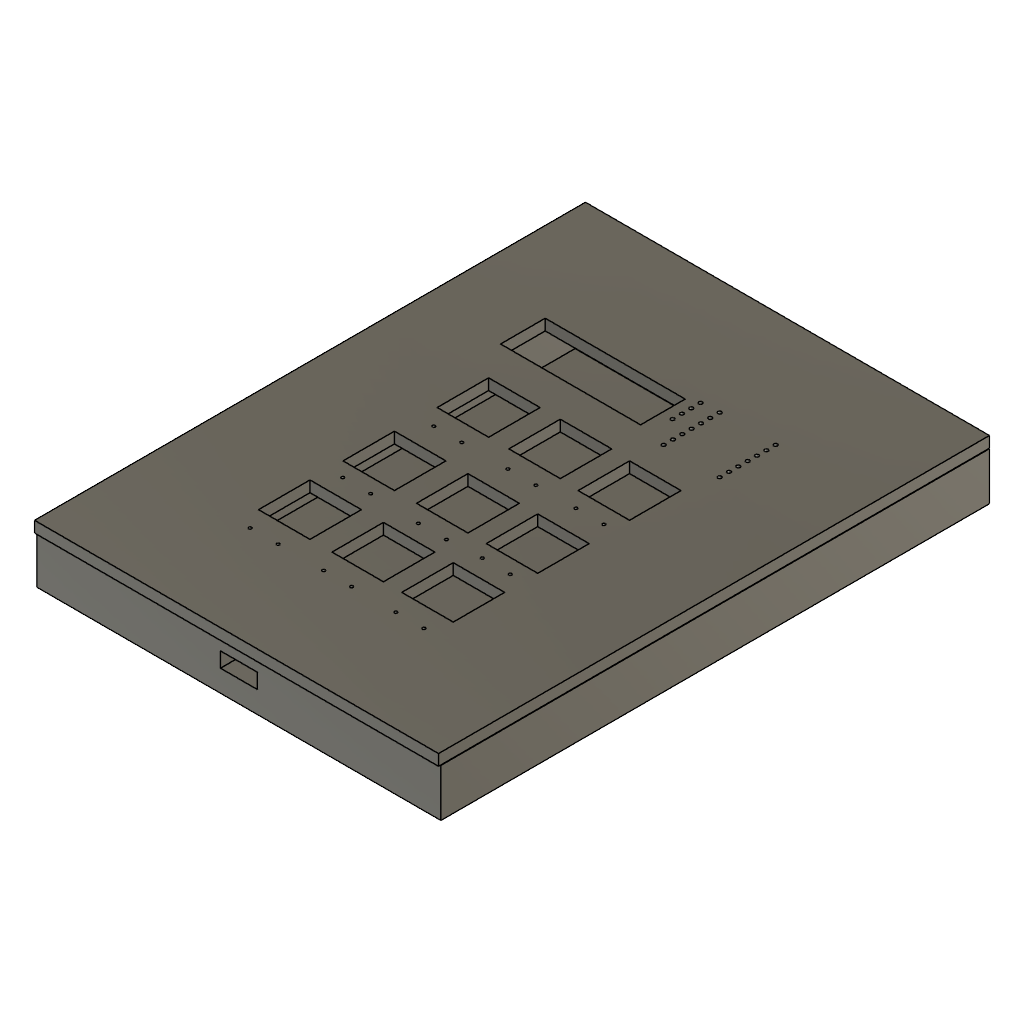
Macropad (Autodesk Fusion 360 design; units mm, degrees)
description: KiCad electronic assembly
part number: Macropad 1
part number: D_DO-35_SOD27_P7.62mm_Horizontal
Autodesk Fusion 360 part; units mm, degrees
sketch "Sketch1" plane through (0, 0, 0) normal (0, 0, 1) x (1, 0, 0)
  line L0 (86, -18, 1.51) -> (154.9049, -18, 1.51)
  line L1 (154.9049, -18, 1.51) -> (154.9049, -127.13, 1.51)
  line L2 (154.9049, -127.13, 1.51) -> (86, -127.13, 1.51)
  line L3 (86, -127.13, 1.51) -> (86, -18, 1.51)
  line L4 (69.7264, -4.9403) -> (170.0821, -4.9403)
  line L5 (170.0821, -4.9403) -> (170.0821, -139.9403)
  line L6 (170.0821, -139.9403) -> (69.7264, -139.9403)
  line L7 (69.7264, -139.9403) -> (69.7264, -4.9403)
  line L8 (-50, -10) -> (18.3484, -10)
  line L9 (18.3484, -10) -> (18.3484, -119.13)
  line L10 (18.3484, -119.13) -> (-50, -119.13)
  line L11 (-50, -119.13) -> (-50, -10)
  line L12 (-70, 10) -> (40, 10)
  line L13 (40, 10) -> (40, -139.3672)
  line L14 (40, -139.3672) -> (-70, -139.3672)
  line L15 (-70, -139.3672) -> (-70, 10)
  circle A0 centre (-60, 0) radius 1.45
  circle A1 centre (30, 0) radius 1.45
  circle A2 centre (30, -130) radius 1.45
  circle A3 centre (-60, -130) radius 1.45
  dimension "d1" = 109.13
  dimension "d2" = 135
  dimension "d3" = 109.13
  dimension "d5" = 2.9
  dimension "d6" = 2.9
  dimension "d7" = 2.9
  dimension "d8" = 2.9
  constraint horizontal L4
  constraint vertical L5
  constraint horizontal L6
  constraint vertical L7
  constraint horizontal L8
  constraint vertical L9
  constraint horizontal L10
  constraint vertical L11
  constraint horizontal L12
  constraint vertical L13
  constraint horizontal L14
  constraint vertical L15
  measures "d2" distance of L4.start L6.end
  measures "d3" distance of L8.start L10.end
  measures "d5" diameter of A0
  measures "d6" diameter of A1
  measures "d7" diameter of A2
  measures "d8" diameter of A3
extrude "Extrude1" add sketch "Sketch1" along normal blind 3 contours L8 L9 L10 L11 | L12 L13 L14 L15 makes body 1
sketch "Sketch2" plane through (0, 0, 3) normal (0, 0, 1) x (-1, 0, 0)
  circle A0 centre (60, 0) radius 1.45
  circle A1 centre (-30, 130) radius 1.45
  circle A2 centre (-30, 0) radius 1.45
  circle A3 centre (60, 130) radius 1.45
  line L0 (70, 139.3672) -> (-40, 139.3672)
  line L1 (-40, 139.3672) -> (-40, -10)
  line L2 (-40, -10) -> (70, -10)
  line L3 (70, -10) -> (70, 139.3672)
  line L4 (70, -10) -> (-40, -10)
  line L5 (-40, -10) -> (-40, 140)
  line L6 (-40, 140) -> (70, 140)
  line L7 (70, 140) -> (70, -10)
  line L8 (50, 12.8137) -> (-20.5069, 12.8137)
  line L9 (-20.5069, 12.8137) -> (-20.5069, 121.9437)
  line L10 (-20.5069, 121.9437) -> (50, 121.9437)
  line L11 (50, 121.9437) -> (50, 12.8137)
  dimension "d11" = 150
  dimension "d12" = 109.13
  constraint horizontal L4
  constraint vertical L5
  constraint horizontal L6
  constraint vertical L7
  constraint coincident L2.end L3.start
  constraint horizontal L8
  constraint vertical L9
  constraint horizontal L10
  constraint vertical L11
  measures "d11" distance of L2.end L6.end
  measures "d12" distance of L8.start L10.end
extrude "Extrude2" add sketch "Sketch2" along normal blind 10 contours L0 L1 L2 L3 L4 L5 L7 bodies 1
sketch "Sketch3" plane through (0, 0, 37.1086) normal (0, 0, 1) x (-1, 0, 0)
  line L0 (49.5053, 121.9681) -> (-19.4947, 121.9681)
  line L1 (-19.4947, 121.9681) -> (-19.4947, 12.9681)
  line L2 (-19.4947, 12.9681) -> (49.5053, 12.9681)
  line L3 (49.5053, 12.9681) -> (49.5053, 121.9681)
  circle A0 centre (38.8153, 112.4681) radius 0.4
  circle A1 centre (31.1953, 112.4681) radius 0.4
  circle A2 centre (40.1653, 99.9681) radius 0.85
  circle A3 centre (38.8953, 97.4281) radius 0.75
  circle A4 centre (35.0853, 99.9681) radius 2
  circle A5 centre (30.0053, 99.9681) radius 0.85
  circle A6 centre (32.5453, 94.8881) radius 0.75
  circle A7 centre (18.8153, 112.4681) radius 0.4
  circle A8 centre (21.0853, 99.9681) radius 0.85
  circle A9 centre (19.8153, 97.4281) radius 0.75
  circle A10 centre (16.0053, 99.9681) radius 2
  circle A11 centre (38.1253, 87.9681) radius 0.4
  circle A12 centre (30.5053, 87.9681) radius 0.4
  circle A13 centre (40.1653, 76.4681) radius 0.85
  circle A14 centre (38.8953, 73.9281) radius 0.75
  circle A15 centre (35.0853, 76.4681) radius 2
  circle A16 centre (30.0053, 76.4681) radius 0.85
  circle A17 centre (32.5453, 71.3881) radius 0.75
  circle A18 centre (17.0053, 88.4681) radius 0.4
  circle A19 centre (20.6653, 76.4681) radius 0.85
  circle A20 centre (19.3953, 73.9281) radius 0.75
  circle A21 centre (15.5853, 76.4681) radius 2
  circle A22 centre (11.1953, 112.4681) radius 0.4
  circle A23 centre (10.9253, 99.9681) radius 0.85
  circle A24 centre (13.4653, 94.8881) radius 0.75
  circle A25 centre (1.5853, 99.9681) radius 0.85
  circle A26 centre (0.3153, 97.4281) radius 0.75
  circle A27 centre (-0.8747, 112.4681) radius 0.4
  circle A28 centre (-8.4947, 112.4681) radius 0.4
  circle A29 centre (-3.4947, 99.9681) radius 2
  circle A30 centre (-6.0347, 94.8881) radius 0.75
  circle A31 centre (-8.5747, 99.9681) radius 0.85
  circle A32 centre (9.3853, 88.4681) radius 0.4
  circle A33 centre (0.1253, 87.9681) radius 0.4
  circle A34 centre (10.5053, 76.4681) radius 0.85
  circle A35 centre (13.0453, 71.3881) radius 0.75
  circle A36 centre (1.6653, 76.4681) radius 0.85
  circle A37 centre (0.3953, 73.9281) radius 0.75
  circle A38 centre (-7.4947, 87.9681) radius 0.4
  circle A39 centre (-3.4147, 76.4681) radius 2
  circle A40 centre (-5.9547, 71.3881) radius 0.75
  circle A41 centre (-8.4947, 76.4681) radius 0.85
  circle A42 centre (37.8153, 63.4681) radius 0.4
  circle A43 centre (30.1953, 63.4681) radius 0.4
  circle A44 centre (40.0853, 51.4681) radius 0.85
  circle A45 centre (35.0053, 51.4681) radius 2
  circle A46 centre (38.8153, 48.9281) radius 0.75
  circle A47 centre (29.9253, 51.4681) radius 0.85
  circle A48 centre (32.4653, 46.3881) radius 0.75
  circle A49 centre (17.6253, 63.4681) radius 0.4
  circle A50 centre (20.5853, 51.4681) radius 0.85
  circle A51 centre (15.5053, 51.4681) radius 2
  circle A52 centre (19.3153, 48.9281) radius 0.75
  circle A53 centre (10.0053, 63.4681) radius 0.4
  circle A54 centre (10.4253, 51.4681) radius 0.85
  circle A55 centre (12.9653, 46.3881) radius 0.75
  circle A56 centre (1.1653, 51.4681) radius 0.85
  circle A57 centre (-0.8747, 63.4681) radius 0.4
  circle A58 centre (-8.4947, 63.4681) radius 0.4
  circle A59 centre (-3.9147, 51.4681) radius 2
  circle A60 centre (-0.1047, 48.9281) radius 0.75
  circle A61 centre (-6.4547, 46.3881) radius 0.75
  circle A62 centre (-8.9947, 51.4681) radius 0.85
  circle A63 centre (2.1303, 36.5881) radius 0.5
  circle A64 centre (2.1303, 34.0481) radius 0.5
  circle A65 centre (7.0053, 29.2781) radius 0.5
  circle A66 centre (7.0053, 26.7381) radius 0.5
  circle A67 centre (7.0053, 24.1981) radius 0.5
  circle A68 centre (7.0053, 21.6581) radius 0.5
  circle A69 centre (2.1303, 31.5081) radius 0.5
  circle A70 centre (2.1303, 28.9681) radius 0.5
  circle A71 centre (2.1303, 26.4281) radius 0.5
  circle A72 centre (2.1303, 23.8881) radius 0.5
  circle A73 centre (2.1303, 21.3481) radius 0.5
  circle A74 centre (-13.1197, 36.5881) radius 0.5
  circle A75 centre (-13.1197, 34.0481) radius 0.5
  circle A76 centre (-13.1197, 31.5081) radius 0.5
  circle A77 centre (-13.1197, 28.9681) radius 0.5
  circle A78 centre (-13.1197, 26.4281) radius 0.5
  circle A79 centre (-13.1197, 23.8881) radius 0.5
  circle A80 centre (-13.1197, 21.3481) radius 0.5
  line L4 (70, -10) -> (-40, -10)
  line L5 (-40, -10) -> (-40, 140)
  line L6 (-40, 140) -> (70, 140)
  line L7 (70, 140) -> (70, -10)
  line L8 (-19.4947, 121.9681) -> (49.5053, 121.9681)
  line L9 (41.7673, 44.6043) -> (27.757, 44.6043)
  line L10 (27.757, 44.6043) -> (27.757, 58.6043)
  line L11 (27.757, 58.6043) -> (41.7673, 58.6043)
  line L12 (41.7673, 58.6043) -> (41.7673, 44.6043)
  line L13 (22.2576, 44.6043) -> (8.2473, 44.6043)
  line L14 (8.2473, 44.6043) -> (8.2473, 58.6043)
  line L15 (8.2473, 58.6043) -> (22.2576, 58.6043)
  line L16 (22.2576, 58.6043) -> (22.2576, 44.6043)
  line L17 (3, 45) -> (-11, 45)
  line L18 (-11, 45) -> (-11, 59)
  line L19 (-11, 59) -> (3, 59)
  line L20 (3, 59) -> (3, 45)
  line L21 (42, 70) -> (28, 70)
  line L22 (28, 70) -> (28, 84)
  line L23 (28, 84) -> (42, 84)
  line L24 (42, 84) -> (42, 70)
  line L25 (22, 70) -> (8, 70)
  line L26 (8, 70) -> (8, 84)
  line L27 (8, 84) -> (22, 84)
  line L28 (22, 84) -> (22, 70)
  line L29 (3, 70) -> (-11, 70)
  line L30 (-11, 70) -> (-11, 84)
  line L31 (-11, 84) -> (3, 84)
  line L32 (3, 84) -> (3, 70)
  line L33 (42, 93) -> (28, 93)
  line L34 (28, 93) -> (28, 107)
  line L35 (28, 107) -> (42, 107)
  line L36 (42, 107) -> (42, 93)
  line L37 (22, 93) -> (8, 93)
  line L38 (8, 93) -> (8, 107)
  line L39 (8, 107) -> (22, 107)
  line L40 (22, 107) -> (22, 93)
  line L41 (3, 93) -> (-11, 93)
  line L42 (-11, 93) -> (-11, 107)
  line L43 (-11, 107) -> (3, 107)
  line L44 (3, 107) -> (3, 93)
  line L45 (10, 35) -> (48.1118, 35)
  line L46 (48.1118, 35) -> (48.1118, 22.8531)
  line L47 (48.1118, 22.8531) -> (10, 22.8531)
  line L48 (10, 22.8531) -> (10, 35)
  dimension "d15" = 14
  constraint horizontal L4
  constraint vertical L5
  constraint horizontal L6
  constraint vertical L7
  constraint horizontal L8
  constraint coincident L0.end L1.start
  constraint horizontal L9
  constraint vertical L10
  constraint horizontal L11
  constraint vertical L12
  constraint horizontal L13
  constraint vertical L14
  constraint horizontal L15
  constraint vertical L16
  constraint horizontal L17
  constraint vertical L18
  constraint horizontal L19
  constraint vertical L20
  constraint horizontal L21
  constraint vertical L22
  constraint horizontal L23
  constraint vertical L24
  constraint horizontal L25
  constraint vertical L26
  constraint horizontal L27
  constraint vertical L28
  constraint horizontal L29
  constraint vertical L30
  constraint horizontal L31
  constraint vertical L32
  constraint horizontal L33
  constraint vertical L34
  constraint horizontal L35
  constraint vertical L36
  constraint horizontal L37
  constraint vertical L38
  constraint horizontal L39
  constraint vertical L40
  constraint horizontal L41
  constraint vertical L42
  constraint horizontal L43
  constraint vertical L44
  constraint horizontal L45
  constraint vertical L46
  constraint horizontal L47
  constraint vertical L48
  measures "d15" distance of L9.start L11.end
extrude "Extrude3" add sketch "Sketch3" along normal blind 3 separate body contours L0 L1 L2 L3 L8 | L4 L5 L6 L7 makes body 2
move_body "Move1" bodies 2 to x (1, 0, 0) y (0, 1, 0) z (0, 0, 1) at (0, 0, -3)
move_body "Move2" bodies 2 to x (1, 0, 0) y (0, 1, 0) z (0, 0, 1) at (0, 0, -20)
move_body "Move3" bodies 2 to x (1, 0, 0) y (0, 1, 0) z (0, 0, 1) at (0, 0, -1)
sketch "Sketch4" plane through (0, -139.3672, 0) normal (0, -1, 0) x (1, 0, 0)
  line L0 (-70, 0) -> (40, 0)
  line L1 (40, 0) -> (40, 13)
  line L2 (40, 13) -> (-70, 13)
  line L3 (-70, 13) -> (-70, 0)
  line L4 (-20, 10) -> (-9.9539, 10)
  line L5 (-9.9539, 10) -> (-9.9539, 5.9174)
  line L6 (-9.9539, 5.9174) -> (-20, 5.9174)
  line L7 (-20, 5.9174) -> (-20, 10)
  constraint horizontal L4
  constraint vertical L5
  constraint horizontal L6
  constraint vertical L7
extrude "Extrude4" cut sketch "Sketch4" against normal blind 10 contours L4 L5 L6 L7 bodies 1
component "D_DO-35_SOD27_P7.62mm_Horizontal (1)" placed x (-1, 0, 0) y (0, -1, 0) z (0, 0, 1) at (125.5, -68.5, 1.595)
component "D_DO-35_SOD27_P7.62mm_Horizontal (1)" placed x (-1, 0, 0) y (0, -1, 0) z (0, 0, 1) at (105, -93, 1.595)
component "D_DO-35_SOD27_P7.62mm_Horizontal (1)" placed x (-1, 0, 0) y (0, -1, 0) z (0, 0, 1) at (6.549, -162.5513, 5.295)
component "D_DO-35_SOD27_P7.62mm_Horizontal (1)" placed x (-1, 0, 0) y (0, -1, 0) z (0, 0, 1) at (143, -93, 1.595)
component "D_DO-35_SOD27_P7.62mm_Horizontal (1)" placed x (-1, 0, 0) y (0, -1, 0) z (0, 0, 1) at (126.12, -93.5, 1.595)
component "D_DO-35_SOD27_P7.62mm_Horizontal (1)" placed x (-1, 0, 0) y (0, -1, 0) z (0, 0, 1) at (144, -68.5, 1.595)
component "D_DO-35_SOD27_P7.62mm_Horizontal (1)" placed x (-1, 0, 0) y (0, -1, 0) z (0, 0, 1) at (105.31, -68.5, 1.595)
component "D_DO-35_SOD27_P7.62mm_Horizontal (1)" placed x (-1, 0, 0) y (0, -1, 0) z (0, 0, 1) at (26.239, -162.5513, 5.295)
component "D_DO-35_SOD27_P7.62mm_Horizontal (1)" placed x (-1, 0, 0) y (0, -1, 0) z (0, 0, 1) at (104.31, -117.5, 1.595)
